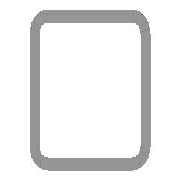
# Autodesk Inventor part: DIN EN 10219-2 - 100 x 100 x 5  - 130
Saved by Autodesk Inventor 2025.3 (Build 293356000, 356)
## iProperties
IsCustomPart: 1
Created: 2024-01-20
Part Number: DIN EN 10219-2 - 100 x 100 x 5  - 130
Material: ABS-Kunststoff
Description: Kaltgeformte, geschweißte Baustahl-Hohlprofile aus unlegiertem Feinkorn-Baustahl
Document SubType Name: Modeling
Standard: DIN EN 10219-2
Designer: trist
Standard Revision: 2006-07
Standards Organization: DIN
Language: de-DE
Size Designation: 100 x 100 x 5  - 130
Categories: <MemberInstance><Categories><Category DisplayName="Profile" InternalName="089c4875-fa83-4c05-b084-43b9cc11f5ed" Mnemonic="GRDR"><CategoryParameter DisplayName="Masse pro Längeneinheit" InternalName="0bb95a10-148f-4027-a459-38d7b056702a" Mnemonic="shpmass"/><CategoryParameter DisplayName="Querschnittsfläche" InternalName="1ff91680-64b0-4202-b9a3-7fd3f94bba3b" Mnemonic="secarea"/><CategoryParameter DisplayName="Trägheitsradius (x)" InternalName="25778675-03e9-40c1-b6a8-4a9ed693320d" Mnemonic="gyrradx"/><CategoryParameter DisplayName="Torsion-Festigkeitsmodul" InternalName="26c1ec35-5026-4c63-ad0a-751cf684a536" Mnemonic="torrigmod"/><CategoryParameter DisplayName="Abstand zum Schwerpunkt X-X" InternalName="26c9bdb8-9c79-4b4f-a92e-8e197583c9c4" Mnemonic="grcendistX"/><CategoryParameter DisplayName="Alte Varianten-ID" InternalName="340afe4f-75d7-48d3-ab7d-943f3c3da468" Mnemonic="LegacyMemberID"/><CategoryParameter DisplayName="Basislänge" InternalName="42e34263-8f20-4d0e-ad48-bf1385b87c24" Mnemonic="shplen"/><CategoryParameter DisplayName="Trägheitsmoment (y)" InternalName="4b9f58ea-bced-460e-81ea-3d29ca5a49e3" Mnemonic="inermomy"/><CategoryParameter DisplayName="Trägheitsmoment (x)" InternalName="4cd780bc-73d7-43ac-917a-579e5cbd684d" Mnemonic="inermomx"/><CategoryParameter DisplayName="Benutzerdefinierter Basispunkt" InternalName="4f1d1b73-316d-484b-a3df-9cbabb16eb77" Mnemonic="shpBasePoint"/><CategoryParameter DisplayName="Objekthöhe" InternalName="50274e7d-5ac0-4796-92cb-c59e54983c67" Mnemonic="shpheig"/><CategoryParameter DisplayName="Widerstandsmoment (y)" InternalName="59eaa5e9-d227-48dc-b6c1-6920f96e0f95" Mnemonic="secmody"/><CategoryParameter DisplayName="Schnittbezeichnung" InternalName="5a64d034-428d-49c8-ba32-7619764de20f" Mnemonic="shpdes"/><CategoryParameter DisplayName="Widerstandsmoment (x)" InternalName="72cfad18-cf51-4ed4-aaa7-c6b224f8419f" Mnemonic="secmodx"/><CategoryParameter DisplayName="Drehrissmodul" InternalName="7c55a8dc-8844-49f9-a867-cc677b30ec9a" Mnemonic="torsecmod"/><CategoryParameter DisplayName="Objektbreite" InternalName="7c717d54-a18f-4666-b4d4-573cce22c62c" Mnemonic="shpwdth"/><CategoryParameter DisplayName="Zweite Objektdicke" InternalName="9251a8e1-85fd-4e47-af99-afdb762317d9" Mnemonic="shpthick2"/><CategoryParameter DisplayName="GG Erstellt" InternalName="9c666724-f362-4ea7-ac62-f6a007de5c69" Mnemonic="shpFGAuto"/><CategoryParameter DisplayName="Abstand zum Schwerpunkt Y-Y" InternalName="bcc4fb17-7af4-436a-8f8c-d0aa3b0248c5" Mnemonic="grcendistY"/><CategoryParameter DisplayName="Trägheitsradius (y)" InternalName="bfa18ebe-1636-4dbe-8d42-b263e0b73184" Mnemonic="gyrrady"/><CategoryParameter DisplayName="Objektdicke" InternalName="d109cf76-8eb4-42fc-9800-4409734adc67" Mnemonic="shpthick"/><CategoryParameter DisplayName="Koeffizient für Schubverschiebung" InternalName="de4c90c6-aaa8-468f-a335-6737b311b5d3" Mnemonic="shdispc"/><Category DisplayName="Vierkantrohre (quadratisch/rechteckig)" InternalName="afc8e2d8-05d6-4609-8807-f98a9b7d2ed0" Mnemonic="SQRSHP"><CategoryParameter DisplayName="Querschnittsfläche" InternalName="2f7f79dd-983c-4263-802a-5b6a1495fdc5" Mnemonic="secarea"/><CategoryParameter DisplayName="Widerstandsmoment (x)" InternalName="50d965a6-04bf-46b9-8ace-861858d348e6" Mnemonic="secmodx"/><CategoryParameter DisplayName="Widerstandsmoment (y)" InternalName="5106aeac-54a2-4159-a9af-8933dd39dba2" Mnemonic="secmody"/><CategoryParameter DisplayName="Objektdicke" InternalName="52712fc5-f4ee-4eda-b3f2-6fce82c26419" Mnemonic="shpthick"/><CategoryParameter DisplayName="Trägheitsmoment (y)" InternalName="55ec8510-8276-4c45-8f10-594e0fee7eb3" Mnemonic="inermomy"/><CategoryParameter DisplayName="Trägheitsradius (x)" InternalName="56c89926-a299-4389-a862-ac94c9691272" Mnemonic="gyrradx"/><CategoryParameter DisplayName="Radius" InternalName="5d8d062c-e28e-41c1-98da-8e5fee36da1a" Mnemonic="shprad"/><CategoryParameter DisplayName="Trägheitsmoment (x)" InternalName="8c4637b6-6b69-4878-9d5d-26a32185d655" Mnemonic="inermomx"/><CategoryParameter DisplayName="Objektbreite" InternalName="8c8a1782-5e80-4d77-858b-304b1c0ad1fd" Mnemonic="shpwdth"/><CategoryParameter DisplayName="Trägheitsradius (y)" InternalName="fa48a7f5-f030-40f9-a60b-de8a845b7104" Mnemonic="gyrrady"/></Category></Category><Category DisplayName="Datentyp" InternalName="23b78d0f-2648-40c6-8793-ca6db495c9e8" Mnemonic="DATATYPE"><CategoryParameter DisplayName="Anzeigename" InternalName="05415f3d-3907-474b-a020-eb9d644f4cf3" Mnemonic="DISPLAYNAME"/><CategoryParameter DisplayName="Norm" InternalName="0c0a119c-1e12-4c84-803f-101930972f5e" Mnemonic="STANDARD"/><CategoryParameter DisplayName="Beschreibung" InternalName="13903e3d-64b1-4950-80da-f627842ea37f" Mnemonic="DESCRIPTION"/><CategoryParameter DisplayName="Bezeichnung" InternalName="2675968c-4ce5-49e0-a4f5-552d29089031" Mnemonic="DESIGNATION"/><CategoryParameter DisplayName="Standardzeile" InternalName="2af9ec52-faaa-4026-b378-f9fa4afca842" Mnemonic="DEFAULTROW"/><CategoryParameter DisplayName="Ordnername" InternalName="3f06958e-8713-4116-9be7-ed6184ecc97b" Mnemonic="FOLDERNAME"/><CategoryParameter DisplayName="Revisionsanleitung" InternalName="45a75005-10b1-4dfc-8d6d-dfe629f0b93c" Mnemonic="REVISIONGUID"/><CategoryParameter DisplayName="Dateiname" InternalName="8b46a4cc-9585-4fed-90c3-899f57e09a73" Mnemonic="FILENAME"/><CategoryParameter DisplayName="Normungsorganisation" InternalName="8f5914e1-4693-403f-8ab5-d37768198c9d" Mnemonic="STDSORG"/><CategoryParameter DisplayName="Gruppenversion" InternalName="914462f6-6e19-4b14-ba84-155b9680b1d0" Mnemonic="FAMILYREVISION"/><CategoryParameter DisplayName="Normrevision" InternalName="91d5a463-65c2-4fde-b823-3b7fea5e8e17" Mnemonic="STANDARDREVISION"/><CategoryParameter DisplayName="Variantenrevision" InternalName="a65d44b9-392f-4f4f-857b-e4b3d54996fe" Mnemonic="MEMBERREVISION"/><CategoryParameter DisplayName="ClipFormat" InternalName="bc51e27b-3422-4e78-93ef-cec197ddf230" Mnemonic="CLIPFORMAT"/><CategoryParameter DisplayName="Hersteller" InternalName="cd6c7a72-a28a-4e50-99a9-2c7f4e13e5ad" Mnemonic="MANUFACTURER"/><CategoryParameter DisplayName="InternerName" InternalName="cf1d0246-76d9-4b4a-8305-fa0409afb5c1" Mnemonic="INTERNALNAME"/><CategoryParameter DisplayName="IstMetrisch" InternalName="e2385c5b-1ea4-4823-96a8-8de651266ec3" Mnemonic="ISMETRIC"/><Category DisplayName="Bauteil" InternalName="c0e0b642-3bcb-4cc8-9e80-f96d35c4afa4" Mnemonic="PART"><CategoryParameter DisplayName="Bauteilnummer" InternalName="016b6077-bfbe-49bd-92c9-d8d59c39c941" Mnemonic="PARTNUMBER"/><CategoryParameter DisplayName="Bestandsnummer" InternalName="4dba7c1c-e26c-444e-836c-b08b433409a8" Mnemonic="STOCKNUMBER"/><CategoryParameter DisplayName="Materialschlüssel" InternalName="5c9a8adb-dd2b-4535-b97f-0a94a95fe41f" Mnemonic="MATERIALKEY"/><CategoryParameter DisplayName="Material" InternalName="818a152a-d3c3-49ca-80ee-df7d91421b8e" Mnemonic="MATERIAL"/></Category></Category><Category DisplayName="ÄltereVersionenzuweisen" InternalName="cd87c42b-3e48-431e-b5c0-1cbeb14dfe77" Mnemonic="LEGACYMAP"><CategoryParameter DisplayName="Eindeutige DA-Varianten-ID" InternalName="0918ad47-427f-4fed-ae26-24c81c58f590" Mnemonic="DACOOKIE"/><CategoryParameter DisplayName="ID zusammenführen" InternalName="0ee8fb18-e2ed-4f39-96f6-1f4b5f50aa71" Mnemonic="MERGE11"/><CategoryParameter DisplayName="Eindeutige CC-Varianten-ID" InternalName="5193edd4-b2b0-4ab4-9d54-de900eee34e0" Mnemonic="CCCOOKIE"/><CategoryParameter DisplayName="ID aufteilen" InternalName="72b5c83c-be7f-45c4-ae51-9160ea6deb26" Mnemonic="SPLIT"/><CategoryParameter DisplayName="VarianteID" InternalName="8e5e0294-fc51-4c8f-b3d7-003dc5ed94f6" Mnemonic="MEMBERID"/><CategoryParameter DisplayName="Katalogname" InternalName="d99d1e27-aa94-4de2-af4c-c348882a6f4f" Mnemonic="CATALOGNAME"/><CategoryParameter DisplayName="Gruppennummer" InternalName="e705e1f4-09cb-413e-91f9-551b4188271e" Mnemonic="FAMILYNUMBER"/></Category></Categories><FamilyTemplate Id="gp0601"><FamilyTemplateParameters><FamilyTemplateParameter ObjectType="kUserParameterObject" ValueType="xs:double" Id="1" ObjectReferenceKey="G_H"/><FamilyTemplateParameter ObjectType="kUserParameterObject" ValueType="xs:double" Id="2" ObjectReferenceKey="B_L"/><FamilyTemplateParameter ObjectType="kUserParameterObject" ValueType="xs:double" Id="6" ObjectReferenceKey="G_W"/><FamilyTemplateParameter ObjectType="kUserParameterObject" ValueType="xs:double" Id="7" ObjectReferenceKey="G_T"/><FamilyTemplateParameter ObjectType="kUserParameterObject" ValueType="xs:double" Id="8" ObjectReferenceKey="G_IR"/><FamilyTemplateParameter ObjectType="kPropertyObject" ValueType="xs:string" Id="100" ObjectReferenceKey="{32853F0F-3444-11d1-9E93-0060B03C1CA6}" SubObjectId="52"/><FamilyTemplateParameter ObjectType="kPropertyObject" ValueType="xs:string" Id="105" ObjectReferenceKey="{32853F0F-3444-11d1-9E93-0060B03C1CA6}" SubObjectId="5"/><FamilyTemplateParameter ObjectType="kPartComponentDefinitionObject" ValueType="xs:string" Id="110" SubObjectId="Material"/><FamilyTemplateParameter ObjectType="kPropertyObject" ValueType="xs:string" Id="112" ObjectReferenceKey="{32853F0F-3444-11d1-9E93-0060B03C1CA6}" SubObjectId="55"/></FamilyTemplateParameters></FamilyTemplate><CategoryParameterMap><ParamToTemplateMap><ParamToTemplate CategoryParameter="//CategoryParameter[@InternalName='05415f3d-3907-474b-a020-eb9d644f4cf3']" ConstantValue="DIN EN 10219-2 (Square Hollow Section - Cold Formed)"/><ParamToTemplate CategoryParameter="//CategoryParameter[@InternalName='cf1d0246-76d9-4b4a-8305-fa0409afb5c1']" ConstantValue="f4eb4807-7530-48bf-9740-f5a60eee53a8"/><ParamToTemplate CategoryParameter="//CategoryParameter[@InternalName='3f06958e-8713-4116-9be7-ed6184ecc97b']" ConstantValue="DIN EN 10219-2(1)"/><ParamToTemplate CategoryParameter="//CategoryParameter[@InternalName='914462f6-6e19-4b14-ba84-155b9680b1d0']" ConstantValue="10"/><ParamToTemplate CategoryParameter="//CategoryParameter[@InternalName='bc51e27b-3422-4e78-93ef-cec197ddf230']" ConstantValue="CF_INVENTOR.STDPARTS"/><ParamToTemplate CategoryParameter="//CategoryParameter[@InternalName='e2385c5b-1ea4-4823-96a8-8de651266ec3']" ConstantValue="true"/><ParamToTemplate CategoryParameter="//CategoryParameter[@InternalName='13903e3d-64b1-4950-80da-f627842ea37f']" ConstantValue="Cold formed welded structural hollow sections of non-alloy and fine grain structural steel"/><ParamToTemplate CategoryParameter="//CategoryParameter[@InternalName='8f5914e1-4693-403f-8ab5-d37768198c9d']" ConstantValue="DIN"/><ParamToTemplate CategoryParameter="//CategoryParameter[@InternalName='0c0a119c-1e12-4c84-803f-101930972f5e']" ConstantValue="DIN EN 10219-2"/><ParamToTemplate CategoryParameter="//CategoryParameter[@InternalName='cd6c7a72-a28a-4e50-99a9-2c7f4e13e5ad']" TemplateParameter="104"/><ParamToTemplate CategoryParameter="//CategoryParameter[@InternalName='91d5a463-65c2-4fde-b823-3b7fea5e8e17']" ConstantValue="2006-07"/><ParamToTemplate CategoryParameter="//CategoryParameter[@InternalName='45a75005-10b1-4dfc-8d6d-dfe629f0b93c']" ConstantValue="fa0180ad-9900-4c48-9c99-ee51de72b725"/><ParamToTemplate CategoryParameter="//CategoryParameter[@InternalName='2af9ec52-faaa-4026-b378-f9fa4afca842']" ConstantValue="1"/><ParamToTemplate CategoryParameter="//CategoryParameter[@InternalName='9c666724-f362-4ea7-ac62-f6a007de5c69']" ConstantValue="1"/><ParamToTemplate CategoryParameter="//CategoryParameter[@InternalName='d99d1e27-aa94-4de2-af4c-c348882a6f4f']" ConstantValue="BSI"/><ParamToTemplate CategoryParameter="//CategoryParameter[@InternalName='e705e1f4-09cb-413e-91f9-551b4188271e']" ConstantValue="158"/><ParamToTemplate CategoryParameter="//CategoryParameter[@InternalName='8b46a4cc-9585-4fed-90c3-899f57e09a73']" ConstantValue="DIN EN 10219-2 - 100 x 100 x 5  - 130"/><ParamToTemplate CategoryParameter="//CategoryParameter[@InternalName='a65d44b9-392f-4f4f-857b-e4b3d54996fe']" ConstantValue="49229FD5-5431-4EE6-B6F3-2C28CB392A87"/><ParamToTemplate CategoryParameter="//CategoryParameter[@InternalName='8c4637b6-6b69-4878-9d5d-26a32185d655']" ConstantValue="271"/><ParamToTemplate CategoryParameter="//CategoryParameter[@InternalName='56c89926-a299-4389-a862-ac94c9691272']" ConstantValue="38,4"/><ParamToTemplate CategoryParameter="//CategoryParameter[@InternalName='50d965a6-04bf-46b9-8ace-861858d348e6']" ConstantValue="54,2"/><ParamToTemplate CategoryParameter="//CategoryParameter[@InternalName='2f7f79dd-983c-4263-802a-5b6a1495fdc5']" ConstantValue="18,4"/><ParamToTemplate CategoryParameter="//CategoryParameter[@InternalName='7c55a8dc-8844-49f9-a867-cc677b30ec9a']" ConstantValue="81,7"/><ParamToTemplate CategoryParameter="//CategoryParameter[@InternalName='26c1ec35-5026-4c63-ad0a-751cf684a536']" ConstantValue="441"/><ParamToTemplate CategoryParameter="//CategoryParameter[@InternalName='de4c90c6-aaa8-468f-a335-6737b311b5d3']" ConstantValue="2,2219"/><ParamToTemplate CategoryParameter="//CategoryParameter[@InternalName='5a64d034-428d-49c8-ba32-7619764de20f']" ConstantValue="100 x 100 x 5"/><ParamToTemplate CategoryParameter="//CategoryParameter[@InternalName='8e5e0294-fc51-4c8f-b3d7-003dc5ed94f6']" ConstantValue="44"/><ParamToTemplate CategoryParameter="//CategoryParameter[@InternalName='42e34263-8f20-4d0e-ad48-bf1385b87c24']" TemplateParameter="2"/><ParamToTemplate CategoryParameter="//CategoryParameter[@InternalName='2675968c-4ce5-49e0-a4f5-552d29089031']" TemplateParameter="100"/><ParamToTemplate CategoryParameter="//CategoryParameter[@InternalName='50274e7d-5ac0-4796-92cb-c59e54983c67']" TemplateParameter="1"/><ParamToTemplate CategoryParameter="//CategoryParameter[@InternalName='52712fc5-f4ee-4eda-b3f2-6fce82c26419']" TemplateParameter="7"/><ParamToTemplate CategoryParameter="//CategoryParameter[@InternalName='8c8a1782-5e80-4d77-858b-304b1c0ad1fd']" TemplateParameter="6"/><ParamToTemplate CategoryParameter="//CategoryParameter[@InternalName='818a152a-d3c3-49ca-80ee-df7d91421b8e']" TemplateParameter="110"/><ParamToTemplate CategoryParameter="//CategoryParameter[@InternalName='016b6077-bfbe-49bd-92c9-d8d59c39c941']" TemplateParameter="105"/><ParamToTemplate CategoryParameter="//CategoryParameter[@InternalName='4dba7c1c-e26c-444e-836c-b08b433409a8']" TemplateParameter="112"/></ParamToTemplateMap></CategoryParameterMap></MemberInstance>
Stock Number: 100 x 100 x 5
Mass: 235.185 g
Surface Area: 946.367 cm^2
Volume: 221.873 cm^3
Density: 1.06 g/cm^3
Appearance: Glatt - Weiß
G_L: 130,000 mm
Author: trist
Autodesk Inventor part; units mm, degrees
ref_plane "YZ Plane" through (0, 0, 0) normal (1, 0, 0) x (0, 1, 0)
ref_plane "Startebene" through (0, 0, 0) normal (0, 0, 1) x (1, 0, 0)
ref_plane "Endebene" through (0, 0, 130) normal (0, 0, 1) x (1, 0, 0)
sketch "Skizze" plane through (0, 0, 0) normal (0, 0, 1) x (1, 0, 0)
  line L0 (-50, -40) -> (-50, 40)
  line L1 (-40, 50) -> (40, 50)
  line L2 (50, 40) -> (50, -40)
  line L3 (40, -50) -> (-40, -50)
  arc A0 (-50, -40) -> (-40, -50) centre (-40, -40) ccw
  arc A1 (-40, 50) -> (-50, 40) centre (-40, 40) ccw
  arc A2 (50, 40) -> (40, 50) centre (40, 40) ccw
  arc A3 (40, -50) -> (50, -40) centre (40, -40) ccw
  arc A4 (-40, 45) -> (-45, 40) centre (-40, 40) ccw
  line L4 (-40, 45) -> (40, 45)
  arc A5 (45, 40) -> (40, 45) centre (40, 40) ccw
  line L5 (45, 40) -> (45, -40)
  arc A6 (40, -45) -> (45, -40) centre (40, -40) ccw
  line L6 (40, -45) -> (-40, -45)
  arc A7 (-45, -40) -> (-40, -45) centre (-40, -40) ccw
  line L7 (-45, -40) -> (-45, 40)
  line L8 (0, 37.1021) -> (0, -37.1021) construction
  line L9 (-23.1021, 0) -> (23.1021, 0) construction
  dimension "d7" = 10
  dimension "d10" = 100
  dimension "d11" = 100
  dimension "d12" = 5
  dimension "d15" = 50
  dimension "d16" = 50
  constraints: 16 end point, 16 point on circle, 8 centre point, 8 tangent, 4 parallel, 3 equal radius, 2 perpendicular, 7 other
  measures "d7" radius of A0
  measures "d10" distance between parallel lines of L1 L3
  measures "d11" distance between parallel lines of L0 L2
  measures "d12" distance between parallel lines of L2 L5
  measures "d15" distance between parallel lines of L1 L9
  measures "d16" distance between parallel lines of L8 L2
extrude "Körper" add sketch "Skizze" along normal up to surface (130 mm away) from surface at 0
sketch "Sketch3" plane through (0, 0, 0) normal (0, 0, 1) x (1, 0, 0)
  line L0 (0, 0) -> (10, 0)
ref_plane "Work Plane3" through (0, 0, 0) normal (0, -1, 0) x (1, 0, 0)
sketch "Skizze5" plane through (-40, -50, 130) normal (0, 0, 1) x (1, 0, 0)
  line L0 (-30, 50) -> (110, 50) projected
  line L1 (40, -20) -> (40, 120) projected
  line L2 (8.18, 81.82) -> (71.82, 81.82)
  line L3 (71.82, 81.82) -> (71.82, 18.18)
  line L4 (71.82, 18.18) -> (8.18, 18.18)
  line L5 (8.18, 18.18) -> (8.18, 81.82)
  circle A0 centre (8.18, 81.82) radius 3
  circle A1 centre (71.82, 81.82) radius 3
  circle A2 centre (8.18, 18.18) radius 3
  circle A3 centre (71.82, 18.18) radius 3
  line L6 (80, 95) -> (0, 95) projected
  arc A4 (0, 95) -> (-5, 90) centre (0, 90) ccw projected
  line L7 (-5, 90) -> (-5, 10) projected
  arc A5 (-5, 10) -> (0, 5) centre (0, 10) ccw projected
  line L8 (0, 5) -> (80, 5) projected
  arc A6 (80, 5) -> (85, 10) centre (80, 10) ccw projected
  line L9 (85, 10) -> (85, 90) projected
  arc A7 (85, 90) -> (80, 95) centre (80, 90) ccw projected
  line L10 (-5, 95) -> (13, 95)
  line L11 (13, 95) -> (13, 77)
  line L12 (13, 77) -> (-5, 77)
  line L13 (-5, 77) -> (-5, 95)
  line L14 (-5, 5) -> (13, 5)
  line L15 (13, 5) -> (13, 23)
  line L16 (13, 23) -> (-5, 23)
  line L17 (-5, 23) -> (-5, 5)
  line L18 (85, 5) -> (67, 5)
  line L19 (67, 5) -> (67, 23)
  line L20 (67, 23) -> (85, 23)
  line L21 (85, 23) -> (85, 5)
  line L22 (85, 95) -> (67, 95)
  line L23 (67, 95) -> (67, 77)
  line L24 (67, 77) -> (85, 77)
  line L25 (85, 77) -> (85, 95)
  point P0 (40, 50)
  point P1 (85, 77)
  point P2 (67, 5)
  point P3 (85, 23)
  point P4 (-5, 23)
  point P5 (13, 5)
  point P6 (13, 95)
  dimension "d19" = 63.64
  dimension "d20" = 63.64
  dimension "d21" = 6
  dimension "d22" = 6
  dimension "d23" = 6
  dimension "d24" = 6
  dimension "d25" = 18
  dimension "d26" = 18
  dimension "d27" = 18
  dimension "d28" = 18
  dimension "d29" = 18
  dimension "d30" = 18
  dimension "d31" = 18
  dimension "d32" = 18
  constraints: 40 end point, 10 parallel, 5 horizontal, 5 perpendicular, 4 centre point, 4 coincident, 2 point on line, 2 other
  measures "d19" distance of L3.end L4.end
  measures "d20" distance of L2.end L3.end
  measures "d21" diameter of A0
  measures "d22" diameter of A1
  measures "d23" diameter of A2
  measures "d24" diameter of A3
  measures "d25" distance of L11.end L12.end
  measures "d26" distance of L10.end L11.end
  measures "d27" distance of L16.end L15.end
  measures "d28" distance of L15.end L14.end
  measures "d29" distance of L19.end L20.end
  measures "d30" distance of L18.end L19.end
  measures "d31" distance of L24.end L23.end
  measures "d32" distance of L23.end L22.end
extrude "Extrusion2" [suppressed]
sketch "Skizze6" plane through (-40, -50, 130) normal (0, 0, 1) x (1, 0, 0)
  line L0 (80, 95) -> (0, 95) projected
  line L1 (-5, 90) -> (-5, 10) projected
  arc A0 (-5, 10) -> (0, 5) centre (0, 10) ccw projected
  line L2 (-5, 23) -> (-5, 10) projected
  arc A1 (85, 90) -> (80, 95) centre (80, 90) ccw projected
  line L3 (80, 95) -> (67, 95) projected
  line L4 (85, 77) -> (85, 90) projected
  line L5 (-5, 5) -> (85, 5)
  line L6 (85, 5) -> (85, 95)
  line L7 (85, 95) -> (-5, 95)
  line L8 (-5, 95) -> (-5, 5)
  point P0 (40, 50)
  point P1 (13, 95)
  point P2 (-5, 77)
  point P3 (-5, 10)
  point P4 (0, 5)
  point P5 (-5, 10)
  point P6 (80, 95)
  point P7 (85, 90)
  constraints: 8 end point, 2 parallel, 1 horizontal, 1 perpendicular
extrude "Extrusion3" [suppressed]
sketch "Skizze7" plane through (40, 50, 130) normal (0, 1, 0) x (1, 0, 0)
  line L0 (-110, 130) -> (30, 130) projected
  line L1 (-40, 156) -> (-40, -26) projected
  line L2 (-57, 130) -> (-12, 130)
  line L3 (-12, 130) -> (-12, 65)
  line L4 (-12, 65) -> (-57, 65)
  line L5 (-57, 65) -> (-57, 130)
  line L6 (-80, 130) -> (-80, 0) projected
  point P0 (-40, 130)
  point P1 (-12, 97.5)
  point P2 (-40, 65)
  dimension "d37" = 45
  dimension "d38" = 65
  dimension "d39" = 0
  dimension "d40" = 68
  constraints: 8 end point, 2 parallel, 1 horizontal, 1 midpoint, 1 perpendicular
  measures "d37" distance from line of point (-12, 97.5) L5
  measures "d38" distance between parallel lines of L2 L4
  measures "d39" distance between parallel lines of L0 L2
  measures "d40" distance between parallel lines of L6 L3
extrude "Extrusion4" cut sketch "Skizze7" against normal blind 10.5
sketch "Skizze8" plane through (0, 0, 0) normal (0, 0, -1) x (-1, 0, 0)
  line L0 (70, 0) -> (-70, 0) projected
  line L1 (0, -70) -> (0, 70) projected
  line L2 (40, -45) -> (-40, -45) projected
  line L3 (45, 40) -> (45, -40) projected
  line L4 (17, 45) -> (-28, 45) projected
  line L5 (17, 45) -> (40, 45) projected
  line L6 (-45, -40) -> (-45, 40) projected
  line L7 (-45, 27) -> (-27, 27) projected
  line L8 (-27, 27) -> (-27, 45) projected
  circle A0 centre (-31.82, 31.82) radius 3 projected
  arc A1 (-40, 45) -> (-45, 40) centre (-40, 40) ccw projected
  line L9 (-40, 45) -> (-28, 45) projected
  circle A2 centre (31.82, 31.82) radius 3 projected
  line L10 (27, 27) -> (45, 27) projected
  line L11 (27, 45) -> (27, 27) projected
  arc A3 (45, 40) -> (40, 45) centre (40, 40) ccw projected
  line L12 (45, -27) -> (27, -27) projected
  circle A4 centre (31.82, -31.82) radius 3 projected
  line L13 (27, -27) -> (27, -45) projected
  arc A5 (40, -45) -> (45, -40) centre (40, -40) ccw projected
  circle A6 centre (-31.82, -31.82) radius 3 projected
  line L14 (-27, -27) -> (-45, -27) projected
  line L15 (-27, -45) -> (-27, -27) projected
  arc A7 (-45, -40) -> (-40, -45) centre (-40, -40) ccw projected
  circle A8 centre (31.82, -31.82) radius 3
  circle A9 centre (-31.82, -31.82) radius 3
  circle A10 centre (-31.82, 31.82) radius 3
  circle A11 centre (31.82, 31.82) radius 3
  line L16 (45, 27) -> (45, 45) projected
  line L17 (27, 27) -> (45, 27)
  line L18 (45, 27) -> (45, 45)
  line L19 (45, 45) -> (27, 45)
  line L20 (27, 45) -> (27, 27)
  line L21 (27, -27) -> (45, -27)
  line L22 (45, -27) -> (45, -45)
  line L23 (45, -45) -> (27, -45)
  line L24 (27, -45) -> (27, -27)
  line L25 (-27, -27) -> (-45, -27)
  line L26 (-45, -27) -> (-45, -45)
  line L27 (-45, -45) -> (-27, -45)
  line L28 (-27, -45) -> (-27, -27)
  line L29 (-27, 27) -> (-45, 27)
  line L30 (-45, 27) -> (-45, 45)
  line L31 (-45, 45) -> (-27, 45)
  line L32 (-27, 45) -> (-27, 27)
  point P0 (0, 0)
  constraints: 32 end point, 8 parallel, 4 centre point, 4 coincident, 4 concentric, 4 horizontal, 4 perpendicular, 4 point on line
extrude "Extrusion5" [suppressed]
fillet "Rundung3" [suppressed]
sketch "Skizze9" plane through (-40, -50, 0) normal (0, -1, 0) x (1, 0, 0)
  line L0 (20, 125) -> (60, 125)
  line L1 (60, 125) -> (60, 67)
  line L2 (60, 67) -> (20, 67)
  line L3 (20, 67) -> (20, 125)
  line L4 (0, 0) -> (0, 130) projected
  line L5 (80, 0) -> (80, 130) projected
  line L6 (80, 130) -> (0, 130) projected
  line L7 (80, 0) -> (0, 0) projected
  point P0 (40, 125)
  point P1 (40, 115)
  point P2 (40, 85)
  dimension "d50" = 40
  dimension "d51" = 58
  dimension "d52" = 20
  dimension "d53" = 5
  dimension "d54" = 20
  dimension "d56" = 30
  dimension "d57" = 20
  dimension "d142" = 10
  constraints: 8 end point, 2 parallel, 1 horizontal, 1 midpoint, 1 perpendicular
  measures "d50" distance of L1.end L2.end
  measures "d51" distance of L0.end L1.end
  measures "d52" distance between parallel lines of L3 L4
  measures "d53" distance from line of L6 point (40, 125)
  measures "d54" distance from line of L3 point (40, 85)
  measures "d56" distance of point (40, 85) point (40, 115)
  measures "d57" distance from line of L3 point (40, 115)
  measures "d142" distance from line of L0 point (40, 115)
sketch "Skizze10" plane through (-40, 50, 130) normal (0, 1, 0) x (1, 0, 0)
  line L0 (0, 0) -> (80, 0) projected
  line L1 (80, 130) -> (80, 0) projected
  line L2 (0, 130) -> (0, 0) projected
  line L3 (0, 130) -> (23, 130) projected
  line L4 (0, 130) -> (80, 130) projected
  line L5 (60, 25) -> (20, 25)
  line L6 (20, 25) -> (20, 105)
  line L7 (20, 105) -> (60, 105)
  line L8 (60, 105) -> (60, 25)
  point P0 (40, 130)
  point P1 (13, 130)
  point P2 (67, 130)
  point P3 (40, 45)
  point P4 (40, 85)
  point P5 (40, 105)
  dimension "d58" = 40
  dimension "d59" = 80
  dimension "d60" = 20
  dimension "d61" = 25
  dimension "d62" = 20
  dimension "d63" = 20
  dimension "d64" = 40
  dimension "d65" = 20
  constraints: 8 end point, 2 parallel, 1 horizontal, 1 midpoint, 1 perpendicular
  measures "d58" distance between parallel lines of L6 L8
  measures "d59" distance between parallel lines of L5 L7
  measures "d60" distance between parallel lines of L8 L1
  measures "d61" distance between parallel lines of L0 L5
  measures "d62" distance of point (40, 105) point (40, 85)
  measures "d63" distance from line of L8 point (40, 85)
  measures "d64" distance of point (40, 85) point (40, 45)
  measures "d65" distance from line of L6 point (40, 45)
sketch "Skizze11" plane through (-50, 40, 0) normal (-1, 0, 0) x (0, 0, 1)
  line L0 (130, -80) -> (130, 0) projected
  line L1 (0, 0) -> (130, 0) projected
  line L2 (0, -80) -> (130, -80) projected
  line L3 (0, -80) -> (0, 0) projected
  line L4 (125, -20) -> (67, -20)
  line L5 (67, -20) -> (67, -60)
  line L6 (67, -60) -> (125, -60)
  line L7 (125, -60) -> (125, -20)
  point P0 (0, -40)
  point P1 (115, -40)
  point P2 (85, -40)
  dimension "d66" = 58
  dimension "d67" = 40
  dimension "d68" = 20
  dimension "d69" = 5
  dimension "d70" = 10
  dimension "d71" = 20
  dimension "d72" = 30
  dimension "d73" = 20
  constraints: 8 end point, 2 parallel, 1 horizontal, 1 perpendicular
  measures "d66" distance of L6.end L5.end
  measures "d67" distance of L5.end L4.end
  measures "d68" distance between parallel lines of L1 L4
  measures "d69" distance between parallel lines of L0 L7
  measures "d70" distance from line of L7 point (115, -40)
  measures "d71" distance from line of point (115, -40) L4
  measures "d72" distance of point (115, -40) point (85, -40)
  measures "d73" distance from line of L6 point (85, -40)
hole "Bohrung1" at (0, -50, 115) at (0, -50, 85) direction (0, 1, 0) diameter 6.647 depth 15 tip angle 118 thread size "M8x1.25" class "6H" standard "ISO Metric profile"
hole "Bohrung2" at (-50, 0, 115) at (-50, 0, 85) direction (1, 0, 0) diameter 6.647 depth 15 tip angle 118 thread size "M8x1.25" class "6H" standard "ISO Metric profile"
sketch "Skizze13" plane through (50, -40, 130) normal (1, 0, 0) x (0, 0, -1)
  line L0 (0, 80) -> (0, 0) projected
  line L1 (130, 0) -> (0, 0) projected
  line L2 (130, 80) -> (130, 0) projected
  line L3 (130, 80) -> (0, 80) projected
  line L4 (10, 20) -> (90, 20)
  line L5 (90, 20) -> (90, 60)
  line L6 (90, 60) -> (10, 60)
  line L7 (10, 60) -> (10, 20)
  circle A0 centre (15, 40) radius 3.3235 projected
  circle A1 centre (45, 40) radius 3.3235 projected
  point P0 (130, 40)
  dimension "d96" = 80
  dimension "d97" = 40
  dimension "d98" = 20
  dimension "d99" = 10
  constraints: 8 end point, 2 coincident, 2 parallel, 1 horizontal, 1 perpendicular
  measures "d96" distance of L6.end L5.end
  measures "d97" distance of L5.end L4.end
  measures "d98" distance between parallel lines of L1 L4
  measures "d99" distance between parallel lines of L0 L7
hole "Bohrung3" at (50, 0, 115) at (50, 0, 85) direction (-1, 0, 0) diameter 6.647 depth 15 tip angle 118 thread size "M8x1.25" class "6H" standard "ISO Metric profile"
chamfer "Fasen1" distance 0.2 angle 45 22 edges at (0, -50, 130) (-47.0711, -47.0711, 130) (-50, 0, 130) (-47.0711, 47.0711, 130) (0, 50, 130) (47.0711, 47.0711, 130) (50, 0, 130) (47.0711, -47.0711, 130) (50, 0, 0) (47.0711, -47.0711, 0) (0, -50, 0) (-47.0711, -47.0711, 0) (-50, 0, 0) (-47.0711, 47.0711, 0) (-28.5, 50, 0) (47.0711, 47.0711, 0) (34, 50, 0) (5.5, 50, 65) (28, 47.5, 0) (-17, 47.5, 0) (28, 50, 32.5) (-17, 50, 32.5)
sketch "Skizze14" plane through (40, -50, 0.2) normal (0, -1, 0) x (1, 0, 0)
  line L0 (-80, 129.6) -> (0, 129.6) projected
  line L1 (10, 0) -> (10, 129.6) projected
  line L2 (-90, 0) -> (-90, 129.6) projected
  line L3 (-40, 129.6) -> (-40, 126.8463)
  line L4 (-40, 126.8463) -> (-40, 0)
  line L5 (0, 0) -> (-80, 0) projected
  point P0 (-40, -0.2)
  point P1 (-71.82, 5)
  point P2 (-8.18, 5)
  point P3 (-71.82, 114.1)
  point P4 (-8.18, 114.1)
  dimension "d110" = 50
  dimension "d111" = 31.82
  dimension "d112" = 63.64
  dimension "d113" = 5
  dimension "d114" = 5
  dimension "d115" = 15.5
  dimension "d116" = 15.5
  dimension "d117" = 63.64
  dimension "d118" = 31.82
  constraints: 4 end point, 1 midpoint, 1 perpendicular, 1 point on line
  measures "d110" distance between parallel lines of L2 L4
  measures "d111" distance from line of point (-71.82, 5) L4
  measures "d112" distance of point (-8.18, 5) point (-71.82, 5)
  measures "d113" distance from line of L5 point (-71.82, 5)
  measures "d114" distance from line of L5 point (-8.18, 5)
  measures "d115" distance from line of L0 point (-8.18, 114.1)
  measures "d116" distance from line of L0 point (-71.82, 114.1)
  measures "d117" distance of point (-8.18, 114.1) point (-71.82, 114.1)
  measures "d118" distance from line of L4 point (-8.18, 114.1)
hole "Bohrung4" at (-31.82, -50, 5.2) at (31.82, -50, 5.2) at (-31.82, -50, 114.3) at (31.82, -50, 114.3) direction (0, 1, 0) diameter 4.134 end through all thread size "M5x0.8" class "6H" standard "ISO Metric profile"
sketch "Skizze15" plane through (50, 40, 129.8) normal (1, 0, 0) x (0, 0, -1)
  line L0 (0, -80) -> (0, 0) projected
  line L1 (129.6, -90) -> (0, -90) projected
  line L2 (129.6, 10) -> (0, 10) projected
  line L3 (129.6, 0) -> (129.6, -80) projected
  line L4 (0, -40) -> (129.8, -40)
  point P0 (124.6, -71.82)
  point P1 (15.5, -71.82)
  point P2 (15.5, -8.18)
  point P3 (124.6, -8.18)
  dimension "d126" = 63.64
  dimension "d127" = 31.82
  dimension "d128" = 5
  dimension "d129" = 5
  dimension "d130" = 63.64
  dimension "d131" = 31.82
  dimension "d132" = 15.5
  dimension "d133" = 15.5
  constraints: 2 end point, 1 horizontal, 1 midpoint
  measures "d126" distance of point (124.6, -71.82) point (124.6, -8.18)
  measures "d127" distance from line of L4 point (124.6, -71.82)
  measures "d128" distance from line of L3 point (124.6, -71.82)
  measures "d129" distance from line of L3 point (124.6, -8.18)
  measures "d130" distance of point (15.5, -71.82) point (15.5, -8.18)
  measures "d131" distance from line of L4 point (15.5, -71.82)
  measures "d132" distance from line of L0 point (15.5, -71.82)
  measures "d133" distance from line of L0 point (15.5, -8.18)
hole "Bohrung5" at (50, -31.82, 5.2) at (50, -31.82, 114.3) at (50, 31.82, 114.3) at (50, 31.82, 5.2) direction (-1, 0, 0) diameter 4.134 end through all thread size "M5x0.8" class "6H" standard "ISO Metric profile"
sketch "Sketch4" plane through (0, 0, 0) normal (0, -1, 0) x (1, 0, 0)
  line L0 (-2, 0) -> (12, 0) projected
  line L1 (-2, 130) -> (12, 130) projected
  dimension "d18" = 130
  measures "d18" distance between parallel lines of L0 L1
equation "\"d7\" = G_IR"
equation "\"d10\" = G_H"
equation "\"d11\" = G_W"
equation "\"d12\" = G_T"
equation "\"d15\" = 0.5 * d10"
equation "\"d16\" = 0.5 * d11"
equation "\"d3\" = G_L"
equation "\"G_W\" = 100"
equation "\"G_H\" = 100"
equation "\"G_T\" = 5"
equation "\"G_IR\" = 10"
equation "\"G_L\" = d18"
equation "\"G_OFFSET_START\" = 0"
equation "\"G_OFFSET_END\" = 0"
body "Solid1"
